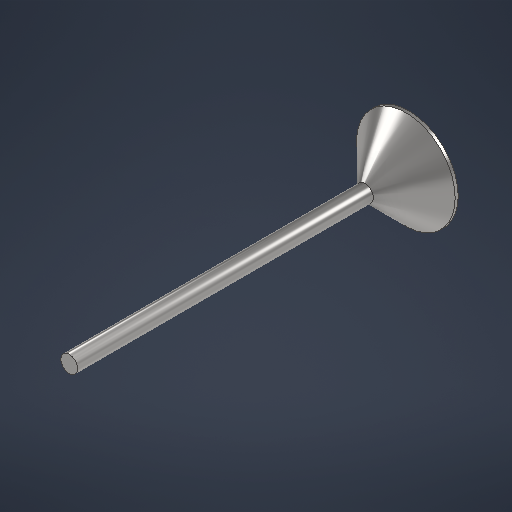
# Autodesk Inventor part: Exhaust_Valve
Saved by Autodesk Inventor 2027.1 (Build 311270010, 270A)
## iProperties
Created: 2026-10-17
Part Number: Exhaust_Valve
Material: Steel, Alloy
Document SubType Name: Modeling
Designer: kashyap
Density: 7.73 g/cm^3
Appearance: Semi-Polished
Mass: 56.6869 g
Surface Area: 36.8522 cm^2
Volume: 7.33337 cm^3
Material_Status: Assumed for this reconstruction
Author: kashyap
Autodesk Inventor part; units mm, degrees
derived "V6_Engine_Master.ipt"
ref_plane "Valve_Face_Plane" through (0, 0, 0) normal (0, 0, 1) x (1, 0, 0)
ref_plane "Valve_Margin_Plane" through (0, 0, 1) normal (0, 0, 1) x (1, 0, 0)
sketch "SK_Head" plane through (0, 0, 0) normal (0, 0, 1) x (1, 0, 0)
  circle A0 centre (0, 0) radius 16
  dimension "d21" = 32
  constraints: 1 centre point
  measures "d21" diameter of A0
extrude "Valve_Head_Margin" add sketch "SK_Head" along normal blind 1
sketch "SK_Face" plane through (0, 0, 1) normal (0, 0, 1) x (1, 0, 0)
  circle A0 centre (0, 0) radius 16
  dimension "d24" = 32
  constraints: 1 centre point
  measures "d24" diameter of A0
extrude "Valve_Seat_Face_45deg" add sketch "SK_Face" along normal blind 13.2638 draft -45
sketch "SK_Stem" plane through (0, 0, 0) normal (0, 0, 1) x (1, 0, 0)
  circle A0 centre (0, 0) radius 2.7363
  dimension "d27" = 5.4725
  constraints: 1 centre point
  measures "d27" diameter of A0
extrude "Valve_Stem" add sketch "SK_Stem" along normal blind 110.4
equation "\"d21\" = Exhaust_Valve_Head_Dia"
equation "\"d22\" = Valve_Margin"
equation "\"d24\" = Exhaust_Valve_Head_Dia"
equation "\"d26\" = -Valve_Face_Angle"
equation "\"d27\" = Exhaust_Valve_Stem_Dia"
equation "\"d28\" = Exhaust_Valve_Length"
equation "\"Exhaust_Valve_Head_Dia\" = 32"
equation "\"Valve_Margin\" = 1"
equation "\"Valve_Face_Angle\" = 45deg"
equation "\"Exhaust_Valve_Stem_Dia\" = 5.4725"
equation "\"Exhaust_Valve_Length\" = 110.4"
body "Solid1"
